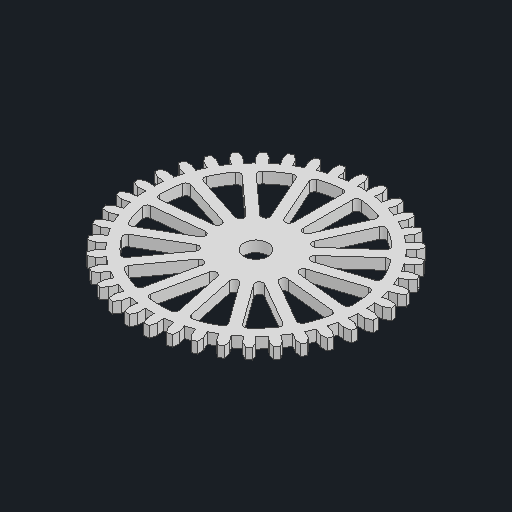
# Autodesk Inventor part: M3_38
Saved by Autodesk Inventor 2027.1 (Build 311270010, 270A)
## iProperties
Created: 2024-04-01
Part Number: M3_38
Material: 一般
Document SubType Name: モデリング
Designer: hibik
Density: 1 g/cm^3
Appearance: 既定
Sheet Metal Rule: Default
Author: hibik
Autodesk Inventor part; units mm, degrees
(part 1 of 2)
ref_plane "YZ Plane" through (0, 0, 0) normal (1, 0, 0) x (0, 1, 0)
ref_plane "XZ Plane" through (0, 0, 0) normal (0, 1, 0) x (-1, 0, 0)
ref_plane "XY Plane" through (0, 0, 0) normal (0, 0, 1) x (1, 0, 0)
sketch "スケッチ1" plane through (0, 0, 0) normal (0, 1, 0) x (-1, 0, 0)
  circle A0 centre (0, 0) radius 57 construction
  circle A1 centre (0, 0) radius 60 construction
  line L0 (60, 1.2454) -> (60, -1.2454)
  line L1 (60, 1.2454) -> (56.9513, 2.355)
  line L2 (60, -1.2454) -> (56.9513, -2.355)
  line L3 (84, 0) -> (-84, 0) projected
  circle A2 centre (0, 0) radius 53.25
  line L4 (56.9513, -2.355) -> (53.2045, -2.2001)
  line L5 (56.9513, 2.355) -> (53.2045, 2.2001)
  line L6 (55.787, 11.6968) -> (52.1168, 10.9272)
  line L7 (58.9767, 11.1041) -> (55.787, 11.6968)
  line L8 (58.9767, 11.1041) -> (59.3867, 8.6473)
  line L9 (59.3867, 8.6473) -> (56.5622, 7.051)
  line L10 (56.5622, 7.051) -> (52.841, 6.5871)
  line L11 (53.1009, 20.7195) -> (49.6074, 19.3563)
  line L12 (56.3447, 20.6599) -> (53.1009, 20.7195)
  line L13 (56.3447, 20.6599) -> (57.1534, 18.3041)
  line L14 (57.1534, 18.3041) -> (54.6302, 16.2647)
  line L15 (54.6302, 16.2647) -> (51.0361, 15.1946)
  line L16 (48.9663, 29.177) -> (45.7449, 27.2575)
  line L17 (52.1757, 29.6521) -> (48.9663, 29.177)
  line L18 (52.1757, 29.6521) -> (53.3612, 27.4616)
  line L19 (53.3612, 27.4616) -> (51.2081, 25.0347)
  line L20 (51.2081, 25.0347) -> (47.8391, 23.3877)
  line L21 (43.4961, 36.8387) -> (40.6345, 34.4151)
  line L22 (46.5835, 37.8355) -> (43.4961, 36.8387)
  line L23 (46.5835, 37.8355) -> (48.1134, 35.87)
  line L24 (48.1134, 35.87) -> (46.3891, 33.1218)
  line L25 (46.3891, 33.1218) -> (43.3372, 30.9427)
  line L26 (36.8395, 43.4955) -> (34.4158, 40.6339)
  line L27 (39.7206, 44.9869) -> (36.8395, 43.4955)
  line L28 (39.7206, 44.9869) -> (41.5531, 43.3)
  line L29 (41.5531, 43.3) -> (40.3047, 40.3055)
  line L30 (40.3047, 40.3055) -> (37.6531, 37.6538)
  line L31 (29.1779, 48.9658) -> (27.2583, 45.7444)
  line L32 (31.7743, 50.9111) -> (29.1779, 48.9658)
  line L33 (31.7743, 50.9111) -> (33.8595, 49.5488)
  line L34 (33.8595, 49.5488) -> (33.121, 46.3897)
  line L35 (33.121, 46.3897) -> (30.9419, 43.3377)
  line L36 (20.7204, 53.1005) -> (19.3573, 49.607)
  line L37 (22.9612, 55.4467) -> (20.7204, 53.1005)
  line L38 (22.9612, 55.4467) -> (25.2422, 54.4461)
  line L39 (25.2422, 54.4461) -> (25.0337, 51.2085)
  line L40 (25.0337, 51.2085) -> (23.3868, 47.8395)
  line L41 (11.6978, 55.7868) -> (10.9282, 52.1166)
  line L42 (13.5219, 58.4697) -> (11.6978, 55.7868)
  line L43 (13.5219, 58.4697) -> (15.9364, 57.8583)
  line L44 (15.9364, 57.8583) -> (16.2637, 54.6305)
  line L45 (16.2637, 54.6305) -> (15.1937, 51.0364)
  line L46 (2.356, 56.9513) -> (2.201, 53.2045)
  line L47 (3.7136, 59.8979) -> (2.356, 56.9513)
  line L48 (3.7136, 59.8979) -> (6.1959, 59.6922)
  line L49 (6.1959, 59.6922) -> (7.05, 56.5623)
  line L50 (7.05, 56.5623) -> (6.5861, 52.8411)
  line L51 (-7.05, 56.5623) -> (-6.5861, 52.8411)
  line L52 (-6.1959, 59.6922) -> (-7.05, 56.5623)
  line L53 (-6.1959, 59.6922) -> (-3.7136, 59.8979)
  line L54 (-3.7136, 59.8979) -> (-2.356, 56.9513)
  line L55 (-2.356, 56.9513) -> (-2.201, 53.2045)
  line L56 (-16.2637, 54.6305) -> (-15.1937, 51.0364)
  line L57 (-15.9364, 57.8583) -> (-16.2637, 54.6305)
  line L58 (-15.9364, 57.8583) -> (-13.5219, 58.4697)
  line L59 (-13.5219, 58.4697) -> (-11.6978, 55.7868)
  line L60 (-11.6978, 55.7868) -> (-10.9282, 52.1166)
  line L61 (-25.0337, 51.2085) -> (-23.3868, 47.8395)
  line L62 (-25.2422, 54.4461) -> (-25.0337, 51.2085)
  line L63 (-25.2422, 54.4461) -> (-22.9612, 55.4467)
  line L64 (-22.9612, 55.4467) -> (-20.7204, 53.1005)
  line L65 (-20.7204, 53.1005) -> (-19.3573, 49.607)
  line L66 (-33.121, 46.3897) -> (-30.9419, 43.3377)
  line L67 (-33.8595, 49.5488) -> (-33.121, 46.3897)
  line L68 (-33.8595, 49.5488) -> (-31.7743, 50.9111)
  line L69 (-31.7743, 50.9111) -> (-29.1779, 48.9658)
  line L70 (-29.1779, 48.9658) -> (-27.2583, 45.7444)
  line L71 (-40.3047, 40.3055) -> (-37.6531, 37.6538)
  line L72 (-41.5531, 43.3) -> (-40.3047, 40.3055)
  line L73 (-41.5531, 43.3) -> (-39.7206, 44.9869)
  line L74 (-39.7206, 44.9869) -> (-36.8395, 43.4955)
  line L75 (-36.8395, 43.4955) -> (-34.4158, 40.6339)
  line L76 (-46.3891, 33.1218) -> (-43.3372, 30.9427)
  line L77 (-48.1134, 35.87) -> (-46.3891, 33.1218)
  line L78 (-48.1134, 35.87) -> (-46.5835, 37.8355)
  line L79 (-46.5835, 37.8355) -> (-43.4961, 36.8387)
  line L80 (-43.4961, 36.8387) -> (-40.6345, 34.4151)
  line L81 (-51.2081, 25.0347) -> (-47.8391, 23.3877)
  line L82 (-53.3612, 27.4616) -> (-51.2081, 25.0347)
  line L83 (-53.3612, 27.4616) -> (-52.1757, 29.6521)
  line L84 (-52.1757, 29.6521) -> (-48.9663, 29.177)
  line L85 (-48.9663, 29.177) -> (-45.7449, 27.2575)
  line L86 (-54.6302, 16.2647) -> (-51.0361, 15.1946)
  line L87 (-57.1534, 18.3041) -> (-54.6302, 16.2647)
  line L88 (-57.1534, 18.3041) -> (-56.3447, 20.6599)
  line L89 (-56.3447, 20.6599) -> (-53.1009, 20.7195)
  line L90 (-53.1009, 20.7195) -> (-49.6074, 19.3563)
  line L91 (-56.5622, 7.051) -> (-52.841, 6.5871)
  line L92 (-59.3867, 8.6473) -> (-56.5622, 7.051)
  line L93 (-59.3867, 8.6473) -> (-58.9767, 11.1041)
  line L94 (-58.9767, 11.1041) -> (-55.787, 11.6968)
  line L95 (-55.787, 11.6968) -> (-52.1168, 10.9272)
  line L96 (-56.9513, -2.355) -> (-53.2045, -2.2001)
  line L97 (-60, -1.2454) -> (-56.9513, -2.355)
  line L98 (-60, -1.2454) -> (-60, 1.2454)
  line L99 (-60, 1.2454) -> (-56.9513, 2.355)
  line L100 (-56.9513, 2.355) -> (-53.2045, 2.2001)
  line L101 (-55.787, -11.6968) -> (-52.1168, -10.9272)
  line L102 (-58.9767, -11.1041) -> (-55.787, -11.6968)
  line L103 (-58.9767, -11.1041) -> (-59.3867, -8.6473)
  line L104 (-59.3867, -8.6473) -> (-56.5622, -7.051)
  line L105 (-56.5622, -7.051) -> (-52.841, -6.5871)
  line L106 (-53.1009, -20.7195) -> (-49.6074, -19.3563)
  line L107 (-56.3447, -20.6599) -> (-53.1009, -20.7195)
  line L108 (-56.3447, -20.6599) -> (-57.1534, -18.3041)
  line L109 (-57.1534, -18.3041) -> (-54.6302, -16.2647)
  line L110 (-54.6302, -16.2647) -> (-51.0361, -15.1946)
  line L111 (-48.9663, -29.177) -> (-45.7449, -27.2575)
  line L112 (-52.1757, -29.6521) -> (-48.9663, -29.177)
  line L113 (-52.1757, -29.6521) -> (-53.3612, -27.4616)
  line L114 (-53.3612, -27.4616) -> (-51.2081, -25.0347)
  line L115 (-51.2081, -25.0347) -> (-47.8391, -23.3877)
  line L116 (-43.4961, -36.8387) -> (-40.6345, -34.4151)
  line L117 (-46.5835, -37.8355) -> (-43.4961, -36.8387)
  line L118 (-46.5835, -37.8355) -> (-48.1134, -35.87)
  line L119 (-48.1134, -35.87) -> (-46.3891, -33.1218)
  line L120 (-46.3891, -33.1218) -> (-43.3372, -30.9427)
  line L121 (-36.8395, -43.4955) -> (-34.4158, -40.6339)
  line L122 (-39.7206, -44.9869) -> (-36.8395, -43.4955)
  line L123 (-39.7206, -44.9869) -> (-41.5531, -43.3)
  line L124 (-41.5531, -43.3) -> (-40.3047, -40.3055)
  line L125 (-40.3047, -40.3055) -> (-37.6531, -37.6538)
  line L126 (-29.1779, -48.9658) -> (-27.2583, -45.7444)
  line L127 (-31.7743, -50.9111) -> (-29.1779, -48.9658)
  line L128 (-31.7743, -50.9111) -> (-33.8595, -49.5488)
  line L129 (-33.8595, -49.5488) -> (-33.121, -46.3897)
  line L130 (-33.121, -46.3897) -> (-30.9419, -43.3377)
  line L131 (-20.7204, -53.1005) -> (-19.3573, -49.607)
  line L132 (-22.9612, -55.4467) -> (-20.7204, -53.1005)
  line L133 (-22.9612, -55.4467) -> (-25.2422, -54.4461)
  line L134 (-25.2422, -54.4461) -> (-25.0337, -51.2085)
  line L135 (-25.0337, -51.2085) -> (-23.3868, -47.8395)
  line L136 (-11.6978, -55.7868) -> (-10.9282, -52.1166)
  line L137 (-13.5219, -58.4697) -> (-11.6978, -55.7868)
  line L138 (-13.5219, -58.4697) -> (-15.9364, -57.8583)
  line L139 (-15.9364, -57.8583) -> (-16.2637, -54.6305)
  line L140 (-16.2637, -54.6305) -> (-15.1937, -51.0364)
  line L141 (-2.356, -56.9513) -> (-2.201, -53.2045)
  line L142 (-3.7136, -59.8979) -> (-2.356, -56.9513)
  line L143 (-3.7136, -59.8979) -> (-6.1959, -59.6922)
  line L144 (-6.1959, -59.6922) -> (-7.05, -56.5623)
  line L145 (-7.05, -56.5623) -> (-6.5861, -52.8411)
  line L146 (7.05, -56.5623) -> (6.5861, -52.8411)
  line L147 (6.1959, -59.6922) -> (7.05, -56.5623)
  line L148 (6.1959, -59.6922) -> (3.7136, -59.8979)
  line L149 (3.7136, -59.8979) -> (2.356, -56.9513)
  line L150 (2.356, -56.9513) -> (2.201, -53.2045)
  line L151 (16.2637, -54.6305) -> (15.1937, -51.0364)
  line L152 (15.9364, -57.8583) -> (16.2637, -54.6305)
  line L153 (15.9364, -57.8583) -> (13.5219, -58.4697)
  line L154 (13.5219, -58.4697) -> (11.6978, -55.7868)
  line L155 (11.6978, -55.7868) -> (10.9282, -52.1166)
  line L156 (25.0337, -51.2085) -> (23.3868, -47.8395)
  line L157 (25.2422, -54.4461) -> (25.0337, -51.2085)
  line L158 (25.2422, -54.4461) -> (22.9612, -55.4467)
  line L159 (22.9612, -55.4467) -> (20.7204, -53.1005)
  line L160 (20.7204, -53.1005) -> (19.3573, -49.607)
  line L161 (33.121, -46.3897) -> (30.9419, -43.3377)
  line L162 (33.8595, -49.5488) -> (33.121, -46.3897)
  line L163 (33.8595, -49.5488) -> (31.7743, -50.9111)
  line L164 (31.7743, -50.9111) -> (29.1779, -48.9658)
  line L165 (29.1779, -48.9658) -> (27.2583, -45.7444)
  line L166 (40.3047, -40.3055) -> (37.6531, -37.6538)
  line L167 (41.5531, -43.3) -> (40.3047, -40.3055)
  line L168 (41.5531, -43.3) -> (39.7206, -44.9869)
  line L169 (39.7206, -44.9869) -> (36.8395, -43.4955)
  line L170 (36.8395, -43.4955) -> (34.4158, -40.6339)
  line L171 (46.3891, -33.1218) -> (43.3372, -30.9427)
  line L172 (48.1134, -35.87) -> (46.3891, -33.1218)
  line L173 (48.1134, -35.87) -> (46.5835, -37.8355)
  line L174 (46.5835, -37.8355) -> (43.4961, -36.8387)
  line L175 (43.4961, -36.8387) -> (40.6345, -34.4151)
  line L176 (51.2081, -25.0347) -> (47.8391, -23.3877)
  line L177 (53.3612, -27.4616) -> (51.2081, -25.0347)
  line L178 (53.3612, -27.4616) -> (52.1757, -29.6521)
  line L179 (52.1757, -29.6521) -> (48.9663, -29.177)
  line L180 (48.9663, -29.177) -> (45.7449, -27.2575)
  line L181 (54.6302, -16.2647) -> (51.0361, -15.1946)
  line L182 (57.1534, -18.3041) -> (54.6302, -16.2647)
  line L183 (57.1534, -18.3041) -> (56.3447, -20.6599)
  line L184 (56.3447, -20.6599) -> (53.1009, -20.7195)
  line L185 (53.1009, -20.7195) -> (49.6074, -19.3563)
  line L186 (56.5622, -7.051) -> (52.841, -6.5871)
  line L187 (59.3867, -8.6473) -> (56.5622, -7.051)
  line L188 (59.3867, -8.6473) -> (58.9767, -11.1041)
  line L189 (58.9767, -11.1041) -> (55.787, -11.6968)
  line L190 (55.787, -11.6968) -> (52.1168, -10.9272)
  circle A3 centre (0, 0) radius 11
  point P0 (60, 0)
  point P1 (59.1817, 9.8757)
  point P2 (56.749, 19.482)
  point P3 (52.7684, 28.5568)
  point P4 (47.3484, 36.8528)
  point P5 (40.6369, 44.1434)
  point P6 (32.8169, 50.23)
  point P7 (24.1017, 54.9464)
  point P8 (14.7291, 58.164)
  point P9 (4.9548, 59.7951)
  point P10 (-4.9548, 59.7951)
  point P11 (-14.7291, 58.164)
  point P12 (-24.1017, 54.9464)
  point P13 (-32.8169, 50.23)
  point P14 (-40.6369, 44.1434)
  point P15 (-47.3484, 36.8528)
  point P16 (-52.7684, 28.5568)
  point P17 (-56.749, 19.482)
  point P18 (-59.1817, 9.8757)
  point P19 (-60, 0)
  point P20 (-59.1817, -9.8757)
  point P21 (-56.749, -19.482)
  point P22 (-52.7684, -28.5568)
  point P23 (-47.3484, -36.8528)
  point P24 (-40.6369, -44.1434)
  point P25 (-32.8169, -50.23)
  point P26 (-24.1017, -54.9464)
  point P27 (-14.7291, -58.164)
  point P28 (-4.9548, -59.7951)
  point P29 (4.9548, -59.7951)
  point P30 (14.7291, -58.164)
  point P31 (24.1017, -54.9464)
  point P32 (32.8169, -50.23)
  point P33 (40.6369, -44.1434)
  point P34 (47.3484, -36.8528)
  point P35 (52.7684, -28.5568)
  point P36 (56.749, -19.482)
  point P37 (59.1817, -9.8757)
  point P38 (-43.3372, -30.9427)
  point P39 (-40.6345, -34.4151)
  point P40 (-37.6531, -37.6538)
  point P41 (-34.4158, -40.6339)
  point P42 (-30.9419, -43.3377)
  point P43 (-19.3573, -49.607)
  point P44 (-15.1937, -51.0364)
  point P45 (-10.9282, -52.1166)
  point P46 (-6.5861, -52.8411)
  point P47 (-2.201, -53.2045)
  point P48 (2.201, -53.2045)
  point P49 (10.9282, -52.1166)
  point P50 (15.1937, -51.0364)
  point P51 (19.3573, -49.607)
  point P52 (23.3868, -47.8395)
  point P53 (27.2583, -45.7444)
  point P54 (30.9419, -43.3377)
  point P55 (34.4158, -40.6339)
  point P56 (37.6531, -37.6538)
  point P57 (40.6345, -34.4151)
  point P58 (43.3372, -30.9427)
  point P59 (45.7449, -27.2575)
  point P60 (47.8391, -23.3877)
  point P61 (49.6074, -19.3563)
  point P62 (51.0361, -15.1946)
  point P63 (52.1168, -10.9272)
  point P64 (52.841, -6.5871)
  point P65 (52.841, 6.5871)
  point P66 (52.1168, 10.9272)
  point P67 (49.6074, 19.3563)
  point P68 (45.7449, 27.2575)
  point P69 (40.6345, 34.4151)
  point P70 (37.6531, 37.6538)
  point P71 (34.4158, 40.6339)
  point P72 (27.2583, 45.7444)
  point P73 (19.3573, 49.607)
  point P74 (15.1937, 51.0364)
  point P75 (10.9282, 52.1166)
  point P76 (6.5861, 52.8411)
  point P77 (2.201, 53.2045)
  point P78 (-2.201, 53.2045)
  point P79 (-6.5861, 52.8411)
  point P80 (-10.9282, 52.1166)
  point P81 (-15.1937, 51.0364)
  point P82 (-19.3573, 49.607)
  point P83 (-23.3868, 47.8395)
  point P84 (-27.2583, 45.7444)
  point P85 (-30.9419, 43.3377)
  point P86 (-34.4158, 40.6339)
  point P87 (-37.6531, 37.6538)
  point P88 (-43.3372, 30.9427)
  point P89 (-45.7449, 27.2575)
  point P90 (-47.8391, 23.3877)
  point P91 (-49.6074, 19.3563)
  point P92 (-51.0361, 15.1946)
  point P93 (-52.1168, 10.9272)
  point P94 (-52.841, -6.5871)
  point P95 (-52.1168, -10.9272)
  point P96 (-51.0361, -15.1946)
  point P97 (-49.6074, -19.3563)
  point P98 (-47.8391, -23.3877)
  dimension "d5" = 106.5
  dimension "d0" = 114
  dimension "d1" = 120
  dimension "d3" = 20
  dimension "d4" = 20
  dimension "d14" = 4.71
  dimension "d18" = 360
  dimension "d24" = 22
  constraints: 380 end point, 77 point on line, 6 coincident, 3 centre point, 2 point on circle, 1 midpoint, 1 tangent, 1 vertical, 496 other
  measures "d0" diameter of A0
  measures "d1" diameter of A1
  measures "d3" angle of L3 L1
  measures "d4" angle of L3 L2
  measures "d14" distance of L2.end L1.end
  measures "d24" diameter of A3
extrude "押し出し1" add sketch "スケッチ1" along normal blind 5.5 contours L0 L3 A2 L5 L1 | L0 L2 L4 A2 L3 | A2 L3 A3 | L3 A3 A2 | A2 L6 L7 L8 L9 L10 | L186 L187 L188 L189 L190 A2 | A2 L96 L97 L98 L3 | L3 L98 L99 L100 A2 | A2 L11 L12 L13 L14 L15 | L181 L182 L183 L184 L185 A2 | L91 L92 L93 L94 L95 A2 | A2 L101 L102 L103 L104 L105 | A2 L16 L17 L18 L19 L20 | L176 L177 L178 L179 L180 A2 | L86 L87 L88 L89 L90 A2 | A2 L106 L107 L108 L109 L110 | A2 L21 L22 L23 L24 L25 | L171 L172 L173 L174 L175 A2 | L81 L82 L83 L84 L85 A2 | A2 L111 L112 L113 L114 L115 | A2 L26 L27 L28 L29 L30 | L166 L167 L168 L169 L170 A2 | L76 L77 L78 L79 L80 A2 | A2 L116 L117 L118 L119 L120 | A2 L31 L32 L33 L34 L35 | L161 L162 L163 L164 L165 A2 | L71 L72 L73 L74 L75 A2 | A2 L121 L122 L123 L124 L125 | A2 L36 L37 L38 L39 L40 | L156 L157 L158 L159 L160 A2 | L66 L67 L68 L69 L70 A2 | A2 L126 L127 L128 L129 L130 | A2 L41 L42 L43 L44 L45 | L151 L152 L153 L154 L155 A2 | L61 L62 L63 L64 L65 A2 | A2 L131 L132 L133 L134 L135 | A2 L46 L47 L48 L49 L50 | L146 L147 L148 L149 L150 A2 | L56 L57 L58 L59 L60 A2 | A2 L136 L137 L138 L139 L140 | A2 L51 L52 L53 L54 L55 | L141 L142 L143 L144 L145 A2
sketch "スケッチ2" plane through (0, 5.5, 0) normal (0, 1, 0) x (1, 0, 0)
  circle A0 centre (0, 0) radius 11 projected
  arc A1 (-15.1937, 51.0364) -> (-19.3573, 49.607) centre (0, 0) ccw projected
  circle A2 centre (0, 0) radius 16
  circle A3 centre (0, 0) radius 48.25
  line L0 (-2.5, 48.25) -> (2.5, 48.25) construction
  line L1 (2.5, 48.25) -> (2.5, 0)
  line L2 (2.5, 0) -> (-2.5, 0)
  line L3 (-2.5, 0) -> (-2.5, 48.25)
  point P0 (-2.5, 15.8035)
  point P1 (-2.5, 48.1852)
  point P2 (2.5, 48.1852)
  point P3 (2.5, 15.8035)
  dimension "d25" = 5
  dimension "d26" = 5
  dimension "d27" = 5
  constraints: 8 end point, 3 coincident, 2 centre point, 2 parallel, 1 horizontal, 1 midpoint, 1 perpendicular, 1 tangent
  measures "d25" radial gap between concentric circles of A3 A1
  measures "d26" radial gap between concentric circles of A2 A0
  measures "d27" distance of L0.start L0.end
extrude "押し出し2" cut sketch "スケッチ2" against normal through all contours L1 A3 L3 A2 | A2 L3 A3 L1
sketch "スケッチ4" plane through (0, 5.5, 0) normal (0, 1, 0) x (1, 0, 0)
  line L0 (-2.5, 48.1852) -> (2.5, 48.1852) construction
  line L1 (2.5, 48.1852) -> (2.5, 0)
  line L2 (2.5, 0) -> (-2.5, 0)
  line L3 (-2.5, 0) -> (-2.5, 48.1852)
  circle A0 centre (0, 0) radius 48.25 projected
  circle A1 centre (0, 0) radius 16 projected
  point P0 (-2.5, 15.8035)
  point P1 (2.5, 15.8035)
  point P2 (-2.5, 48.1852)
  dimension "d32" = 5
  constraints: 8 end point, 2 parallel, 1 coincident, 1 horizontal, 1 midpoint, 1 perpendicular, 2 other
  measures "d32" distance of L1.end L2.end
extrude "押し出し4" add sketch "スケッチ4" against normal up to surface (5.5 mm away) contours L1 A1 L3 A0 picked at (0.2779, 26.733)
pattern_circular "円形状パターン1" count 15 over 360 about axis through (0, -10, 0) along (0, 1, 0) of "押し出し4"
fillet "フィレット1" radius 2 4 edges at (7.5729, 2.75, 47.652) (-7.5729, 2.75, 47.652) (0.8404, 2.75, 15.9779) (-0.8404, 2.75, 15.9779)
pattern_circular "円形状パターン2" count 15 over 360 about axis through (0, -10, 0) along (0, 1, 0) of "フィレット1"
sketch "スケッチ5" plane through (0, 0, 0) normal (0, -1, 0) x (1, 0, 0)
  circle A0 centre (0, 0) radius 6 projected
  arc A1 (38.6136, 25.1803) -> (39.2402, 28.0762) centre (37.6136, 26.9124) ccw projected
  line L0 (38.6136, 25.1803) -> (17.0845, 12.7505) projected
  arc A2 (14.4664, 15.6581) -> (17.0845, 12.7505) centre (16.0845, 14.4825) ccw projected
  line L1 (14.4664, 15.6581) -> (29.0786, 35.77) projected
  arc A3 (32.0241, 36.0904) -> (29.0786, 35.77) centre (30.6967, 34.5945) ccw projected
  arc A4 (39.2402, 28.0762) -> (32.0241, 36.0904) centre (0, 0) ccw projected
  arc A5 (21.0062, -41.0342) -> (23.8207, -41.96) centre (22.8333, -40.2207) ccw projected
  line L2 (21.0062, -41.0342) -> (10.8948, -18.3237) projected
  arc A6 (14.0602, -16.0239) -> (10.8948, -18.3237) centre (12.7219, -17.5102) ccw projected
  line L3 (14.0602, -16.0239) -> (32.5345, -32.6583) projected
  arc A7 (32.5453, -35.6211) -> (32.5345, -32.6583) centre (31.1963, -34.1446) ccw projected
  arc A8 (23.8207, -41.96) -> (32.5453, -35.6211) centre (0, 0) ccw projected
  arc A9 (-43.0051, -16.6019) -> (-44.22, -19.3042) centre (-42.3871, -18.504) ccw projected
  line L4 (-43.0051, -16.6019) -> (-19.3621, -8.9198) projected
  arc A10 (-17.4058, -12.3082) -> (-19.3621, -8.9198) centre (-18.7441, -10.8219) ccw projected
  line L5 (-17.4058, -12.3082) -> (-35.8802, -28.9426) projected
  arc A11 (-38.8279, -28.6436) -> (-35.8802, -28.9426) centre (-37.2185, -27.4563) ccw projected
  arc A12 (-44.22, -19.3042) -> (-38.8279, -28.6436) centre (0, 0) ccw projected
  arc A13 (-12.0157, 44.5049) -> (-14.5761, 45.9956) centre (-13.972, 44.0891) ccw projected
  line L6 (-12.0157, 44.5049) -> (-6.847, 20.1884) projected
  arc A14 (-10.4214, 18.597) -> (-6.847, 20.1884) centre (-8.8033, 19.7726) ccw projected
  line L7 (-10.4214, 18.597) -> (-25.0335, 38.709) projected
  arc A15 (-24.4281, 41.6093) -> (-25.0335, 38.709) centre (-23.4155, 39.8845) ccw projected
  arc A16 (-14.5761, 45.9956) -> (-24.4281, 41.6093) centre (0, 0) ccw projected
  arc A17 (-46.0397, 2.3252) -> (-48.2487, 0.3507) centre (-46.2488, 0.3362) ccw projected
  line L8 (-46.0397, 2.3252) -> (-21.3162, -0.2733) projected
  arc A18 (-20.9072, -4.1645) -> (-21.3162, -0.2733) centre (-21.5252, -2.2624) ccw projected
  line L9 (-20.9072, -4.1645) -> (-44.5502, -11.8466) projected
  arc A19 (-47.1215, -10.3745) -> (-44.5502, -11.8466) centre (-45.1682, -9.9445) ccw projected
  arc A20 (-48.2487, 0.3507) -> (-47.1215, -10.3745) centre (0, 0) ccw projected
  arc A21 (2.5, -46.0306) -> (4.6946, -48.0211) centre (4.5, -46.0306) ccw projected
  line L10 (2.5, -46.0306) -> (2.5, -21.1708) projected
  arc A22 (6.3271, -20.3574) -> (2.5, -21.1708) centre (4.5, -21.1708) ccw projected
  line L11 (6.3271, -20.3574) -> (16.4385, -43.0679) projected
  arc A23 (15.2432, -45.7789) -> (16.4385, -43.0679) centre (14.6114, -43.8813) ccw projected
  arc A24 (4.6946, -48.0211) -> (15.2432, -45.7789) centre (0, 0) ccw projected
  arc A25 (45.5171, 7.2978) -> (47.2673, 9.6884) centre (45.308, 9.2869) ccw projected
  line L12 (45.5171, 7.2978) -> (20.7935, 4.6993) projected
  arc A26 (19.5845, 8.4204) -> (20.7935, 4.6993) centre (20.5845, 6.6883) ccw projected
  line L13 (19.5845, 8.4204) -> (41.1136, 20.8502) projected
  arc A27 (43.9348, 19.9449) -> (41.1136, 20.8502) centre (42.1136, 19.1182) ccw projected
  arc A28 (47.2673, 9.6884) -> (43.9348, 19.9449) centre (0, 0) ccw projected
  arc A29 (25.0335, 38.709) -> (24.4281, 41.6093) centre (23.4155, 39.8845) ccw projected
  line L14 (25.0335, 38.709) -> (10.4214, 18.597) projected
  arc A30 (6.847, 20.1884) -> (10.4214, 18.597) centre (8.8033, 19.7726) ccw projected
  line L15 (6.847, 20.1884) -> (12.0157, 44.5049) projected
  arc A31 (14.5761, 45.9956) -> (12.0157, 44.5049) centre (13.972, 44.0891) ccw projected
  arc A32 (24.4281, 41.6093) -> (14.5761, 45.9956) centre (0, 0) ccw projected
  arc A33 (35.8802, -28.9426) -> (38.8279, -28.6436) centre (37.2185, -27.4563) ccw projected
  line L16 (35.8802, -28.9426) -> (17.4058, -12.3082) projected
  arc A34 (19.3621, -8.9198) -> (17.4058, -12.3082) centre (18.7441, -10.8219) ccw projected
  line L17 (19.3621, -8.9198) -> (43.0051, -16.6019) projected
  arc A35 (44.22, -19.3042) -> (43.0051, -16.6019) centre (42.3871, -18.504) ccw projected
  arc A36 (38.8279, -28.6436) -> (44.22, -19.3042) centre (0, 0) ccw projected
  arc A37 (-32.5345, -32.6583) -> (-32.5453, -35.6211) centre (-31.1963, -34.1446) ccw projected
  line L18 (-32.5345, -32.6583) -> (-14.0602, -16.0239) projected
  arc A38 (-10.8948, -18.3237) -> (-14.0602, -16.0239) centre (-12.7219, -17.5102) ccw projected
  line L19 (-10.8948, -18.3237) -> (-21.0062, -41.0342) projected
  arc A39 (-23.8207, -41.96) -> (-21.0062, -41.0342) centre (-22.8333, -40.2207) ccw projected
  arc A40 (-32.5453, -35.6211) -> (-23.8207, -41.96) centre (0, 0) ccw projected
  arc A41 (-29.0786, 35.77) -> (-32.0241, 36.0904) centre (-30.6967, 34.5945) ccw projected
  line L20 (-29.0786, 35.77) -> (-14.4664, 15.6581) projected
  arc A42 (-17.0845, 12.7505) -> (-14.4664, 15.6581) centre (-16.0845, 14.4825) ccw projected
  line L21 (-17.0845, 12.7505) -> (-38.6136, 25.1803) projected
  arc A43 (-39.2402, 28.0762) -> (-38.6136, 25.1803) centre (-37.6136, 26.9124) ccw projected
  arc A44 (-32.0241, 36.0904) -> (-39.2402, 28.0762) centre (0, 0) ccw projected
  arc A45 (-41.1136, 20.8502) -> (-43.9348, 19.9449) centre (-42.1136, 19.1182) ccw projected
  line L22 (-41.1136, 20.8502) -> (-19.5845, 8.4204) projected
  arc A46 (-20.7935, 4.6993) -> (-19.5845, 8.4204) centre (-20.5845, 6.6883) ccw projected
  line L23 (-20.7935, 4.6993) -> (-45.5171, 7.2978) projected
  arc A47 (-47.2673, 9.6884) -> (-45.5171, 7.2978) centre (-45.308, 9.2869) ccw projected
  arc A48 (-43.9348, 19.9449) -> (-47.2673, 9.6884) centre (0, 0) ccw projected
  arc A49 (-16.4385, -43.0679) -> (-15.2432, -45.7789) centre (-14.6114, -43.8813) ccw projected
  line L24 (-16.4385, -43.0679) -> (-6.3271, -20.3574) projected
  arc A50 (-2.5, -21.1708) -> (-6.3271, -20.3574) centre (-4.5, -21.1708) ccw projected
  line L25 (-2.5, -21.1708) -> (-2.5, -46.0306) projected
  arc A51 (-4.6946, -48.0211) -> (-2.5, -46.0306) centre (-4.5, -46.0306) ccw projected
  arc A52 (-15.2432, -45.7789) -> (-4.6946, -48.0211) centre (0, 0) ccw projected
  arc A53 (44.5502, -11.8466) -> (47.1215, -10.3745) centre (45.1682, -9.9445) ccw projected
  line L26 (44.5502, -11.8466) -> (20.9072, -4.1645) projected
  arc A54 (21.3162, -0.2733) -> (20.9072, -4.1645) centre (21.5252, -2.2624) ccw projected
  line L27 (21.3162, -0.2733) -> (46.0397, 2.3252) projected
  arc A55 (48.2487, 0.3507) -> (46.0397, 2.3252) centre (46.2488, 0.3362) ccw projected
  arc A56 (47.1215, -10.3745) -> (48.2487, 0.3507) centre (0, 0) ccw projected
  line L28 (7.1249, 45.5445) -> (1.9563, 21.228) projected
  arc A57 (-1.9563, 21.228) -> (1.9563, 21.228) centre (0, 21.6438) ccw projected
  line L29 (-1.9563, 21.228) -> (-7.1249, 45.5445) projected
  arc A58 (-5.3921, 47.9478) -> (-7.1249, 45.5445) centre (-5.1686, 45.9603) ccw projected
  arc A59 (5.3921, 47.9478) -> (-5.3921, 47.9478) centre (0, 0) ccw projected
  arc A60 (7.1249, 45.5445) -> (5.3921, 47.9478) centre (5.1686, 45.9603) ccw projected
  arc A61 (41.8431, -55.9299) -> (47.5637, -55.3777) centre (44.3103, -51.581) ccw projected
  arc A62 (47.5637, -55.3777) -> (47.5684, -55.3737) centre (0, 0) ccw projected
  arc A63 (47.5684, -55.3737) -> (48.8465, -54.2496) centre (0, 0) ccw projected
  arc A64 (45.7049, -48.9905) -> (48.8465, -54.2496) centre (60.6207, -43.648) ccw projected
  arc A65 (45.7049, -48.9905) -> (52.1817, -42.0246) centre (0, 0) ccw projected
  arc A66 (57.0784, -40.2623) -> (52.1817, -42.0246) centre (56.0759, -45.1607) ccw projected
  arc A67 (57.0784, -40.2623) -> (62.3485, -37.9693) centre (58.081, -35.3638) ccw projected
  arc A68 (62.3485, -37.9693) -> (62.3516, -37.9641) centre (0, 0) ccw projected
  arc A69 (62.3516, -37.9641) -> (63.2199, -36.5) centre (0, 0) ccw projected
  arc A70 (58.6068, -32.4691) -> (63.2199, -36.5) centre (71.1417, -22.7789) ccw projected
  arc A71 (58.6068, -32.4691) -> (62.6141, -23.8427) centre (0, 0) ccw projected
  arc A72 (66.7266, -20.6535) -> (62.6141, -23.8427) centre (67.2868, -25.622) ccw projected
  arc A73 (66.7266, -20.6535) -> (71.0301, -16.8442) centre (66.1663, -15.685) ccw projected
  arc A74 (71.0301, -16.8442) -> (71.0315, -16.8383) centre (0, 0) ccw projected
  arc A75 (71.0315, -16.8383) -> (71.4048, -15.1776) centre (0, 0) ccw projected
  arc A76 (65.7719, -12.7695) -> (71.4048, -15.1776) centre (74.6989, 0.32) ccw projected
  arc A77 (65.7719, -12.7695) -> (66.9173, -3.3269) centre (0, 0) ccw projected
  arc A78 (69.843, 0.977) -> (66.9173, -3.3269) centre (71.9112, -3.5752) ccw projected
  arc A79 (69.843, 0.977) -> (72.7588, 5.9297) centre (67.7748, 5.5292) ccw projected
  arc A80 (72.7588, 5.9297) -> (72.7583, 5.9358) centre (0, 0) ccw projected
  arc A81 (72.7583, 5.9358) -> (72.6001, 7.6306) centre (0, 0) ccw projected
  arc A82 (66.4988, 8.1802) -> (72.6001, 7.6306) centre (70.944, 23.3875) ccw projected
  arc A83 (66.4988, 8.1802) -> (64.6703, 17.5145) centre (0, 0) ccw projected
  arc A84 (66.1227, 22.5119) -> (64.6703, 17.5145) centre (69.4964, 18.8215) ccw projected
  arc A85 (66.1227, 22.5119) -> (67.3653, 28.1232) centre (62.7491, 26.2022) ccw projected
  arc A86 (67.3653, 28.1232) -> (67.363, 28.1288) centre (0, 0) ccw projected
  arc A87 (67.363, 28.1288) -> (66.6888, 29.6918) centre (0, 0) ccw projected
  arc A88 (60.7163, 28.329) -> (66.6888, 29.6918) centre (60.2446, 44.1658) ccw projected
  arc A89 (60.7163, 28.329) -> (55.832, 37.0376) centre (0, 0) ccw projected
  arc A90 (55.6323, 42.238) -> (55.832, 37.0376) centre (59.9986, 39.8016) ccw projected
  arc A91 (55.6323, 42.238) -> (55.0356, 47.9592) centre (51.2661, 44.6743) ccw projected
  arc A92 (55.0356, 47.9592) -> (54.2496, 48.8465) centre (0, 0) ccw projected
  arc A93 (48.9905, 45.7049) -> (54.2496, 48.8465) centre (43.648, 60.6207) ccw projected
  arc A94 (48.9905, 45.7049) -> (41.6542, 52.4779) centre (0, 0) ccw projected
  arc A95 (39.8572, 57.362) -> (41.6542, 52.4779) centre (44.7627, 56.3942) ccw projected
  arc A96 (39.8572, 57.362) -> (37.5218, 62.6188) centre (34.9518, 58.3299) ccw projected
  arc A97 (37.5218, 62.6188) -> (36.5, 63.2199) centre (0, 0) ccw projected
  arc A98 (32.4691, 58.6068) -> (36.5, 63.2199) centre (22.7789, 71.1417) ccw projected
  arc A99 (32.4691, 58.6068) -> (23.3989, 62.7813) centre (0, 0) ccw projected
  arc A100 (20.1806, 66.8711) -> (23.3989, 62.7813) centre (25.1451, 67.4665) ccw projected
  arc A101 (20.1806, 66.8711) -> (16.3351, 71.1489) centre (15.2162, 66.2757) ccw projected
  arc A102 (16.3351, 71.1489) -> (15.1776, 71.4048) centre (0, 0) ccw projected
  arc A103 (12.7695, 65.7719) -> (15.1776, 71.4048) centre (-0.32, 74.6989) ccw projected
  arc A104 (12.7695, 65.7719) -> (3.3269, 66.9173) centre (0, 0) ccw projected
  arc A105 (-0.977, 69.843) -> (3.3269, 66.9173) centre (3.5752, 71.9112) ccw projected
  arc A106 (-0.977, 69.843) -> (-5.9297, 72.7588) centre (-5.5292, 67.7748) ccw projected
  arc A107 (-5.9297, 72.7588) -> (-5.9358, 72.7583) centre (0, 0) ccw projected
  arc A108 (-5.9358, 72.7583) -> (-7.6306, 72.6001) centre (0, 0) ccw projected
  arc A109 (-8.1802, 66.4988) -> (-7.6306, 72.6001) centre (-23.3875, 70.944) ccw projected
  arc A110 (-8.1802, 66.4988) -> (-17.5145, 64.6703) centre (0, 0) ccw projected
  arc A111 (-22.5119, 66.1227) -> (-17.5145, 64.6703) centre (-18.8215, 69.4964) ccw projected
  arc A112 (-22.5119, 66.1227) -> (-28.1232, 67.3653) centre (-26.2022, 62.7491) ccw projected
  arc A113 (-28.1232, 67.3653) -> (-28.1288, 67.363) centre (0, 0) ccw projected
  arc A114 (-28.1288, 67.363) -> (-29.6918, 66.6888) centre (0, 0) ccw projected
  arc A115 (-28.329, 60.7163) -> (-29.6918, 66.6888) centre (-44.1658, 60.2446) ccw projected
  arc A116 (-28.329, 60.7163) -> (-37.0376, 55.832) centre (0, 0) ccw projected
  arc A117 (-42.238, 55.6323) -> (-37.0376, 55.832) centre (-39.8016, 59.9986) ccw projected
  arc A118 (-42.238, 55.6323) -> (-47.9592, 55.0356) centre (-44.6743, 51.2661) ccw projected
  arc A119 (-47.9592, 55.0356) -> (-48.8465, 54.2496) centre (0, 0) ccw projected
  arc A120 (-45.7049, 48.9905) -> (-48.8465, 54.2496) centre (-60.6207, 43.648) ccw projected
  arc A121 (-45.7049, 48.9905) -> (-52.1817, 42.0246) centre (0, 0) ccw projected
  arc A122 (-57.0784, 40.2623) -> (-52.1817, 42.0246) centre (-56.0759, 45.1607) ccw projected
  arc A123 (-57.0784, 40.2623) -> (-62.3485, 37.9693) centre (-58.081, 35.3638) ccw projected
  arc A124 (-62.3485, 37.9693) -> (-62.3516, 37.9641) centre (0, 0) ccw projected
  arc A125 (-62.3516, 37.9641) -> (-63.2199, 36.5) centre (0, 0) ccw projected
  arc A126 (-58.6068, 32.4691) -> (-63.2199, 36.5) centre (-71.1417, 22.7789) ccw projected
  arc A127 (-58.6068, 32.4691) -> (-62.7813, 23.3989) centre (0, 0) ccw projected
  arc A128 (-66.8711, 20.1806) -> (-62.7813, 23.3989) centre (-67.4665, 25.1451) ccw projected
  arc A129 (-66.8711, 20.1806) -> (-71.1489, 16.3351) centre (-66.2757, 15.2162) ccw projected
  arc A130 (-71.1489, 16.3351) -> (-71.4048, 15.1776) centre (0, 0) ccw projected
  arc A131 (-65.7719, 12.7695) -> (-71.4048, 15.1776) centre (-74.6989, -0.32) ccw projected
  arc A132 (-65.7719, 12.7695) -> (-66.9392, 2.8532) centre (0, 0) ccw projected
  arc A133 (-69.8343, -1.4714) -> (-66.9392, 2.8532) centre (-71.9347, 3.0661) ccw projected
  arc A134 (-69.8343, -1.4714) -> (-72.7144, -6.4507) centre (-67.734, -6.0088) ccw projected
  arc A135 (-72.7144, -6.4507) -> (-72.6001, -7.6306) centre (0, 0) ccw projected
  arc A136 (-66.4988, -8.1802) -> (-72.6001, -7.6306) centre (-70.944, -23.3875) ccw projected
  arc A137 (-66.4988, -8.1802) -> (-64.6703, -17.5145) centre (0, 0) ccw projected
  arc A138 (-66.1227, -22.5119) -> (-64.6703, -17.5145) centre (-69.4964, -18.8215) ccw projected
  arc A139 (-66.1227, -22.5119) -> (-67.3653, -28.1232) centre (-62.7491, -26.2022) ccw projected
  arc A140 (-67.3653, -28.1232) -> (-67.363, -28.1288) centre (0, 0) ccw projected
  arc A141 (-67.363, -28.1288) -> (-66.6888, -29.6918) centre (0, 0) ccw projected
  arc A142 (-60.7163, -28.329) -> (-66.6888, -29.6918) centre (-60.2446, -44.1658) ccw projected
  arc A143 (-60.7163, -28.329) -> (-56.0928, -36.6415) centre (0, 0) ccw projected
  arc A144 (-55.9299, -41.8431) -> (-56.0928, -36.6415) centre (-60.2788, -39.3759) ccw projected
  arc A145 (-55.9299, -41.8431) -> (-55.3777, -47.5637) centre (-51.581, -44.3103) ccw projected
  arc A146 (-55.3777, -47.5637) -> (-55.3737, -47.5684) centre (0, 0) ccw projected
  arc A147 (-55.3737, -47.5684) -> (-54.2496, -48.8465) centre (0, 0) ccw projected
  arc A148 (-48.9905, -45.7049) -> (-54.2496, -48.8465) centre (-43.648, -60.6207) ccw projected
  arc A149 (-48.9905, -45.7049) -> (-41.6542, -52.4779) centre (0, 0) ccw projected
  arc A150 (-39.8572, -57.362) -> (-41.6542, -52.4779) centre (-44.7627, -56.3942) ccw projected
  arc A151 (-39.8572, -57.362) -> (-37.5218, -62.6188) centre (-34.9518, -58.3299) ccw projected
  arc A152 (-37.5218, -62.6188) -> (-36.5, -63.2199) centre (0, 0) ccw projected
  arc A153 (-32.4691, -58.6068) -> (-36.5, -63.2199) centre (-22.7789, -71.1417) ccw projected
  arc A154 (-32.4691, -58.6068) -> (-23.8427, -62.6141) centre (0, 0) ccw projected
  arc A155 (-20.6535, -66.7266) -> (-23.8427, -62.6141) centre (-25.622, -67.2868) ccw projected
  arc A156 (-20.6535, -66.7266) -> (-16.8442, -71.0301) centre (-15.685, -66.1663) ccw projected
  arc A157 (-16.8442, -71.0301) -> (-16.8383, -71.0315) centre (0, 0) ccw projected
  arc A158 (-16.8383, -71.0315) -> (-15.1776, -71.4048) centre (0, 0) ccw projected
  arc A159 (-12.7695, -65.7719) -> (-15.1776, -71.4048) centre (0.32, -74.6989) ccw projected
  arc A160 (-12.7695, -65.7719) -> (-2.8532, -66.9392) centre (0, 0) ccw projected
  arc A161 (1.4714, -69.8343) -> (-2.8532, -66.9392) centre (-3.0661, -71.9347) ccw projected
  arc A162 (1.4714, -69.8343) -> (6.4507, -72.7144) centre (6.0088, -67.734) ccw projected
  arc A163 (6.4507, -72.7144) -> (7.6306, -72.6001) centre (0, 0) ccw projected
  arc A164 (8.1802, -66.4988) -> (7.6306, -72.6001) centre (23.3875, -70.944) ccw projected
  arc A165 (8.1802, -66.4988) -> (17.5145, -64.6703) centre (0, 0) ccw projected
  arc A166 (22.5119, -66.1227) -> (17.5145, -64.6703) centre (18.8215, -69.4964) ccw projected
  arc A167 (22.5119, -66.1227) -> (28.1232, -67.3653) centre (26.2022, -62.7491) ccw projected
  arc A168 (28.1232, -67.3653) -> (28.1288, -67.363) centre (0, 0) ccw projected
  arc A169 (28.1288, -67.363) -> (29.6918, -66.6888) centre (0, 0) ccw projected
  arc A170 (28.329, -60.7163) -> (29.6918, -66.6888) centre (44.1658, -60.2446) ccw projected
  arc A171 (28.329, -60.7163) -> (36.6415, -56.0928) centre (0, 0) ccw projected
  arc A172 (41.8431, -55.9299) -> (36.6415, -56.0928) centre (39.3759, -60.2788) ccw projected
  arc A173 (4.6946, -48.0211) -> (15.2432, -45.7789) centre (0, 0) ccw construction
  arc A174 (2.5, -46.0306) -> (4.6946, -48.0211) centre (4.5, -46.0306) ccw construction
  line L30 (2.5, -46.0306) -> (2.5, -21.1708) construction
  arc A175 (6.3271, -20.3574) -> (2.5, -21.1708) centre (4.5, -21.1708) ccw construction
  line L31 (6.3271, -20.3574) -> (16.4385, -43.0679) construction
  arc A176 (15.2432, -45.7789) -> (16.4385, -43.0679) centre (14.6114, -43.8813) ccw construction
  line L32 (21.0062, -41.0342) -> (10.8948, -18.3237) construction
  arc A177 (14.0602, -16.0239) -> (10.8948, -18.3237) centre (12.7219, -17.5102) ccw construction
  line L33 (14.0602, -16.0239) -> (32.5345, -32.6583) construction
  arc A178 (32.5453, -35.6211) -> (32.5345, -32.6583) centre (31.1963, -34.1446) ccw construction
  arc A179 (23.8207, -41.96) -> (32.5453, -35.6211) centre (0, 0) ccw construction
  arc A180 (21.0062, -41.0342) -> (23.8207, -41.96) centre (22.8333, -40.2207) ccw construction
  line L34 (35.8802, -28.9426) -> (17.4058, -12.3082) construction
  arc A181 (19.3621, -8.9198) -> (17.4058, -12.3082) centre (18.7441, -10.8219) ccw construction
  line L35 (19.3621, -8.9198) -> (43.0051, -16.6019) construction
  arc A182 (44.22, -19.3042) -> (43.0051, -16.6019) centre (42.3871, -18.504) ccw construction
  arc A183 (38.8279, -28.6436) -> (44.22, -19.3042) centre (0, 0) ccw construction
  arc A184 (35.8802, -28.9426) -> (38.8279, -28.6436) centre (37.2185, -27.4563) ccw construction
  line L36 (44.5502, -11.8466) -> (20.9072, -4.1645) construction
  arc A185 (21.3162, -0.2733) -> (20.9072, -4.1645) centre (21.5252, -2.2624) ccw construction
  line L37 (21.3162, -0.2733) -> (46.0397, 2.3252) construction
  arc A186 (48.2487, 0.3507) -> (46.0397, 2.3252) centre (46.2488, 0.3362) ccw construction
  arc A187 (47.1215, -10.3745) -> (48.2487, 0.3507) centre (0, 0) ccw construction
  arc A188 (44.5502, -11.8466) -> (47.1215, -10.3745) centre (45.1682, -9.9445) ccw construction
  line L38 (45.5171, 7.2978) -> (20.7935, 4.6993) construction
  arc A189 (19.5845, 8.4204) -> (20.7935, 4.6993) centre (20.5845, 6.6883) ccw construction
  line L39 (19.5845, 8.4204) -> (41.1136, 20.8502) construction
  arc A190 (43.9348, 19.9449) -> (41.1136, 20.8502) centre (42.1136, 19.1182) ccw construction
  arc A191 (47.2673, 9.6884) -> (43.9348, 19.9449) centre (0, 0) ccw construction
  arc A192 (45.5171, 7.2978) -> (47.2673, 9.6884) centre (45.308, 9.2869) ccw construction
  line L40 (38.6136, 25.1803) -> (17.0845, 12.7505) construction
  arc A193 (14.4664, 15.6581) -> (17.0845, 12.7505) centre (16.0845, 14.4825) ccw construction
  line L41 (14.4664, 15.6581) -> (29.0786, 35.77) construction
  arc A194 (32.0241, 36.0904) -> (29.0786, 35.77) centre (30.6967, 34.5945) ccw construction
  arc A195 (39.2402, 28.0762) -> (32.0241, 36.0904) centre (0, 0) ccw construction
  arc A196 (38.6136, 25.1803) -> (39.2402, 28.0762) centre (37.6136, 26.9124) ccw construction
  line L42 (25.0335, 38.709) -> (10.4214, 18.597) construction
  arc A197 (6.847, 20.1884) -> (10.4214, 18.597) centre (8.8033, 19.7726) ccw construction
  line L43 (6.847, 20.1884) -> (12.0157, 44.5049) construction
  arc A198 (14.5761, 45.9956) -> (12.0157, 44.5049) centre (13.972, 44.0891) ccw construction
  arc A199 (24.4281, 41.6093) -> (14.5761, 45.9956) centre (0, 0) ccw construction
  arc A200 (25.0335, 38.709) -> (24.4281, 41.6093) centre (23.4155, 39.8845) ccw construction
  line L44 (7.1249, 45.5445) -> (1.9563, 21.228) construction
  arc A201 (-1.9563, 21.228) -> (1.9563, 21.228) centre (0, 21.6438) ccw construction
  line L45 (-1.9563, 21.228) -> (-7.1249, 45.5445) construction
  arc A202 (-5.3921, 47.9478) -> (-7.1249, 45.5445) centre (-5.1686, 45.9603) ccw construction
  arc A203 (5.3921, 47.9478) -> (-5.3921, 47.9478) centre (0, 0) ccw construction
  arc A204 (7.1249, 45.5445) -> (5.3921, 47.9478) centre (5.1686, 45.9603) ccw construction
  line L46 (-12.0157, 44.5049) -> (-6.847, 20.1884) construction
  arc A205 (-10.4214, 18.597) -> (-6.847, 20.1884) centre (-8.8033, 19.7726) ccw construction
  line L47 (-10.4214, 18.597) -> (-25.0335, 38.709) construction
  arc A206 (-24.4281, 41.6093) -> (-25.0335, 38.709) centre (-23.4155, 39.8845) ccw construction
  arc A207 (-14.5761, 45.9956) -> (-24.4281, 41.6093) centre (0, 0) ccw construction
  arc A208 (-12.0157, 44.5049) -> (-14.5761, 45.9956) centre (-13.972, 44.0891) ccw construction
  line L48 (-29.0786, 35.77) -> (-14.4664, 15.6581) construction
  arc A209 (-17.0845, 12.7505) -> (-14.4664, 15.6581) centre (-16.0845, 14.4825) ccw construction
  line L49 (-17.0845, 12.7505) -> (-38.6136, 25.1803) construction
  arc A210 (-39.2402, 28.0762) -> (-38.6136, 25.1803) centre (-37.6136, 26.9124) ccw construction
  arc A211 (-32.0241, 36.0904) -> (-39.2402, 28.0762) centre (0, 0) ccw construction
  arc A212 (-29.0786, 35.77) -> (-32.0241, 36.0904) centre (-30.6967, 34.5945) ccw construction
  line L50 (-41.1136, 20.8502) -> (-19.5845, 8.4204) construction
  arc A213 (-20.7935, 4.6993) -> (-19.5845, 8.4204) centre (-20.5845, 6.6883) ccw construction
  line L51 (-20.7935, 4.6993) -> (-45.5171, 7.2978) construction
  arc A214 (-47.2673, 9.6884) -> (-45.5171, 7.2978) centre (-45.308, 9.2869) ccw construction
  arc A215 (-43.9348, 19.9449) -> (-47.2673, 9.6884) centre (0, 0) ccw construction
  arc A216 (-41.1136, 20.8502) -> (-43.9348, 19.9449) centre (-42.1136, 19.1182) ccw construction
  line L52 (-46.0397, 2.3252) -> (-21.3162, -0.2733) construction
  arc A217 (-20.9072, -4.1645) -> (-21.3162, -0.2733) centre (-21.5252, -2.2624) ccw construction
  line L53 (-20.9072, -4.1645) -> (-44.5502, -11.8466) construction
  arc A218 (-47.1215, -10.3745) -> (-44.5502, -11.8466) centre (-45.1682, -9.9445) ccw construction
  arc A219 (-48.2487, 0.3507) -> (-47.1215, -10.3745) centre (0, 0) ccw construction
  arc A220 (-46.0397, 2.3252) -> (-48.2487, 0.3507) centre (-46.2488, 0.3362) ccw construction
  line L54 (-43.0051, -16.6019) -> (-19.3621, -8.9198) construction
  arc A221 (-17.4058, -12.3082) -> (-19.3621, -8.9198) centre (-18.7441, -10.8219) ccw construction
  line L55 (-17.4058, -12.3082) -> (-35.8802, -28.9426) construction
  arc A222 (-38.8279, -28.6436) -> (-35.8802, -28.9426) centre (-37.2185, -27.4563) ccw construction
  arc A223 (-44.22, -19.3042) -> (-38.8279, -28.6436) centre (0, 0) ccw construction
  arc A224 (-43.0051, -16.6019) -> (-44.22, -19.3042) centre (-42.3871, -18.504) ccw construction
  line L56 (-32.5345, -32.6583) -> (-14.0602, -16.0239) construction
  arc A225 (-10.8948, -18.3237) -> (-14.0602, -16.0239) centre (-12.7219, -17.5102) ccw construction
  line L57 (-10.8948, -18.3237) -> (-21.0062, -41.0342) construction
  arc A226 (-23.8207, -41.96) -> (-21.0062, -41.0342) centre (-22.8333, -40.2207) ccw construction
  arc A227 (-32.5453, -35.6211) -> (-23.8207, -41.96) centre (0, 0) ccw construction
  arc A228 (-32.5345, -32.6583) -> (-32.5453, -35.6211) centre (-31.1963, -34.1446) ccw construction
  line L58 (-52.841, 6.5871) -> (-56.5622, 7.051) construction
  arc A229 (-52.841, 6.5871) -> (-53.2045, 2.2001) centre (0, 0) ccw construction
  line L59 (-56.9513, 2.355) -> (-53.2045, 2.2001) construction
  line L60 (-60, 1.2454) -> (-56.9513, 2.355) construction
  line L61 (-60, -1.2454) -> (-60, 1.2454) construction
  line L62 (-56.9513, -2.355) -> (-60, -1.2454) construction
  line L63 (-53.2045, -2.2001) -> (-56.9513, -2.355) construction
  arc A230 (-53.2045, -2.2001) -> (-52.841, -6.5871) centre (0, 0) ccw construction
  line L64 (-56.5622, -7.051) -> (-52.841, -6.5871) construction
  line L65 (-59.3867, -8.6473) -> (-56.5622, -7.051) construction
  line L66 (-58.9767, -11.1041) -> (-59.3867, -8.6473) construction
  line L67 (-55.787, -11.6968) -> (-58.9767, -11.1041) construction
  line L68 (-52.1168, -10.9272) -> (-55.787, -11.6968) construction
  arc A231 (-52.1168, -10.9272) -> (-51.0361, -15.1946) centre (0, 0) ccw construction
  line L69 (-54.6302, -16.2647) -> (-51.0361, -15.1946) construction
  line L70 (-57.1534, -18.3041) -> (-54.6302, -16.2647) construction
  line L71 (-56.3447, -20.6599) -> (-57.1534, -18.3041) construction
  line L72 (-53.1009, -20.7195) -> (-56.3447, -20.6599) construction
  line L73 (-49.6074, -19.3563) -> (-53.1009, -20.7195) construction
  arc A232 (-49.6074, -19.3563) -> (-47.8391, -23.3877) centre (0, 0) ccw construction
  line L74 (-51.2081, -25.0347) -> (-47.8391, -23.3877) construction
  line L75 (-53.3612, -27.4616) -> (-51.2081, -25.0347) construction
  line L76 (-52.1757, -29.6521) -> (-53.3612, -27.4616) construction
  line L77 (-48.9663, -29.177) -> (-52.1757, -29.6521) construction
  line L78 (-45.7449, -27.2575) -> (-48.9663, -29.177) construction
  arc A233 (-45.7449, -27.2575) -> (-43.3372, -30.9427) centre (0, 0) ccw construction
  line L79 (-46.3891, -33.1218) -> (-43.3372, -30.9427) construction
  line L80 (-48.1134, -35.87) -> (-46.3891, -33.1218) construction
  line L81 (-46.5835, -37.8355) -> (-48.1134, -35.87) construction
  line L82 (-43.4961, -36.8387) -> (-46.5835, -37.8355) construction
  line L83 (-40.6345, -34.4151) -> (-43.4961, -36.8387) construction
  arc A234 (-40.6345, -34.4151) -> (-37.6531, -37.6538) centre (0, 0) ccw construction
  line L84 (-40.3047, -40.3055) -> (-37.6531, -37.6538) construction
  line L85 (-41.5531, -43.3) -> (-40.3047, -40.3055) construction
  line L86 (-39.7206, -44.9869) -> (-41.5531, -43.3) construction
  line L87 (-36.8395, -43.4955) -> (-39.7206, -44.9869) construction
  line L88 (-34.4158, -40.6339) -> (-36.8395, -43.4955) construction
  arc A235 (-34.4158, -40.6339) -> (-30.9419, -43.3377) centre (0, 0) ccw construction
  line L89 (-33.121, -46.3897) -> (-30.9419, -43.3377) construction
  line L90 (-33.8595, -49.5488) -> (-33.121, -46.3897) construction
  line L91 (-31.7743, -50.9111) -> (-33.8595, -49.5488) construction
  line L92 (-29.1779, -48.9658) -> (-31.7743, -50.9111) construction
  line L93 (-27.2583, -45.7444) -> (-29.1779, -48.9658) construction
  arc A236 (-27.2583, -45.7444) -> (-23.3868, -47.8395) centre (0, 0) ccw construction
  line L94 (-25.0337, -51.2085) -> (-23.3868, -47.8395) construction
  line L95 (-25.2422, -54.4461) -> (-25.0337, -51.2085) construction
  line L96 (-22.9612, -55.4467) -> (-25.2422, -54.4461) construction
  line L97 (-20.7204, -53.1005) -> (-22.9612, -55.4467) construction
  line L98 (-19.3573, -49.607) -> (-20.7204, -53.1005) construction
  arc A237 (-19.3573, -49.607) -> (-15.1937, -51.0364) centre (0, 0) ccw construction
  line L99 (-16.2637, -54.6305) -> (-15.1937, -51.0364) construction
  line L100 (-15.9364, -57.8583) -> (-16.2637, -54.6305) construction
  line L101 (-13.5219, -58.4697) -> (-15.9364, -57.8583) construction
  line L102 (-11.6978, -55.7868) -> (-13.5219, -58.4697) construction
  line L103 (-10.9282, -52.1166) -> (-11.6978, -55.7868) construction
  arc A238 (-10.9282, -52.1166) -> (-6.5861, -52.8411) centre (0, 0) ccw construction
  line L104 (-7.05, -56.5623) -> (-6.5861, -52.8411) construction
  line L105 (-6.1959, -59.6922) -> (-7.05, -56.5623) construction
  line L106 (-3.7136, -59.8979) -> (-6.1959, -59.6922) construction
  line L107 (-2.356, -56.9513) -> (-3.7136, -59.8979) construction
  line L108 (-2.201, -53.2045) -> (-2.356, -56.9513) construction
  arc A239 (-2.201, -53.2045) -> (2.201, -53.2045) centre (0, 0) ccw construction
  line L109 (2.356, -56.9513) -> (2.201, -53.2045) construction
  line L110 (3.7136, -59.8979) -> (2.356, -56.9513) construction
  line L111 (6.1959, -59.6922) -> (3.7136, -59.8979) construction
  line L112 (7.05, -56.5623) -> (6.1959, -59.6922) construction
  line L113 (6.5861, -52.8411) -> (7.05, -56.5623) construction
  arc A240 (6.5861, -52.8411) -> (10.9282, -52.1166) centre (0, 0) ccw construction
  line L114 (11.6978, -55.7868) -> (10.9282, -52.1166) construction
  line L115 (13.5219, -58.4697) -> (11.6978, -55.7868) construction
  line L116 (15.9364, -57.8583) -> (13.5219, -58.4697) construction
  line L117 (16.2637, -54.6305) -> (15.9364, -57.8583) construction
  line L118 (15.1937, -51.0364) -> (16.2637, -54.6305) construction
  arc A241 (15.1937, -51.0364) -> (19.3573, -49.607) centre (0, 0) ccw construction
  line L119 (20.7204, -53.1005) -> (19.3573, -49.607) construction
  line L120 (22.9612, -55.4467) -> (20.7204, -53.1005) construction
  line L121 (25.2422, -54.4461) -> (22.9612, -55.4467) construction
  line L122 (25.0337, -51.2085) -> (25.2422, -54.4461) construction
  line L123 (23.3868, -47.8395) -> (25.0337, -51.2085) construction
  arc A242 (23.3868, -47.8395) -> (27.2583, -45.7444) centre (0, 0) ccw construction
  line L124 (29.1779, -48.9658) -> (27.2583, -45.7444) construction
  line L125 (31.7743, -50.9111) -> (29.1779, -48.9658) construction
  line L126 (33.8595, -49.5488) -> (31.7743, -50.9111) construction
  line L127 (33.121, -46.3897) -> (33.8595, -49.5488) construction
  line L128 (30.9419, -43.3377) -> (33.121, -46.3897) construction
  arc A243 (30.9419, -43.3377) -> (34.4158, -40.6339) centre (0, 0) ccw construction
  line L129 (36.8395, -43.4955) -> (34.4158, -40.6339) construction
  line L130 (39.7206, -44.9869) -> (36.8395, -43.4955) construction
  line L131 (41.5531, -43.3) -> (39.7206, -44.9869) construction
  line L132 (40.3047, -40.3055) -> (41.5531, -43.3) construction
  line L133 (37.6531, -37.6538) -> (40.3047, -40.3055) construction
  arc A244 (37.6531, -37.6538) -> (40.6345, -34.4151) centre (0, 0) ccw construction
  line L134 (43.4961, -36.8387) -> (40.6345, -34.4151) construction
  line L135 (46.5835, -37.8355) -> (43.4961, -36.8387) construction
  line L136 (48.1134, -35.87) -> (46.5835, -37.8355) construction
  line L137 (46.3891, -33.1218) -> (48.1134, -35.87) construction
  line L138 (43.3372, -30.9427) -> (46.3891, -33.1218) construction
  arc A245 (43.3372, -30.9427) -> (45.7449, -27.2575) centre (0, 0) ccw construction
  line L139 (48.9663, -29.177) -> (45.7449, -27.2575) construction
  line L140 (52.1757, -29.6521) -> (48.9663, -29.177) construction
  line L141 (53.3612, -27.4616) -> (52.1757, -29.6521) construction
  line L142 (51.2081, -25.0347) -> (53.3612, -27.4616) construction
  line L143 (47.8391, -23.3877) -> (51.2081, -25.0347) construction
  arc A246 (47.8391, -23.3877) -> (49.6074, -19.3563) centre (0, 0) ccw construction
  line L144 (53.1009, -20.7195) -> (49.6074, -19.3563) construction
  line L145 (56.3447, -20.6599) -> (53.1009, -20.7195) construction
  line L146 (57.1534, -18.3041) -> (56.3447, -20.6599) construction
  line L147 (54.6302, -16.2647) -> (57.1534, -18.3041) construction
  line L148 (51.0361, -15.1946) -> (54.6302, -16.2647) construction
  arc A247 (51.0361, -15.1946) -> (52.1168, -10.9272) centre (0, 0) ccw construction
  line L149 (55.787, -11.6968) -> (52.1168, -10.9272) construction
  line L150 (58.9767, -11.1041) -> (55.787, -11.6968) construction
  line L151 (59.3867, -8.6473) -> (58.9767, -11.1041) construction
  line L152 (56.5622, -7.051) -> (59.3867, -8.6473) construction
  line L153 (52.841, -6.5871) -> (56.5622, -7.051) construction
  arc A248 (52.841, -6.5871) -> (53.2045, -2.2001) centre (0, 0) ccw construction
  line L154 (56.9513, -2.355) -> (53.2045, -2.2001) construction
  line L155 (60, -1.2454) -> (56.9513, -2.355) construction
  line L156 (60, 1.2454) -> (60, -1.2454) construction
  line L157 (56.9513, 2.355) -> (60, 1.2454) construction
  line L158 (53.2045, 2.2001) -> (56.9513, 2.355) construction
  arc A249 (53.2045, 2.2001) -> (52.841, 6.5871) centre (0, 0) ccw construction
  line L159 (56.5622, 7.051) -> (52.841, 6.5871) construction
  line L160 (59.3867, 8.6473) -> (56.5622, 7.051) construction
  line L161 (58.9767, 11.1041) -> (59.3867, 8.6473) construction
  line L162 (55.787, 11.6968) -> (58.9767, 11.1041) construction
  line L163 (52.1168, 10.9272) -> (55.787, 11.6968) construction
  arc A250 (52.1168, 10.9272) -> (51.0361, 15.1946) centre (0, 0) ccw construction
  line L164 (54.6302, 16.2647) -> (51.0361, 15.1946) construction
  line L165 (57.1534, 18.3041) -> (54.6302, 16.2647) construction
  line L166 (56.3447, 20.6599) -> (57.1534, 18.3041) construction
  line L167 (53.1009, 20.7195) -> (56.3447, 20.6599) construction
  line L168 (49.6074, 19.3563) -> (53.1009, 20.7195) construction
  arc A251 (49.6074, 19.3563) -> (47.8391, 23.3877) centre (0, 0) ccw construction
  line L169 (51.2081, 25.0347) -> (47.8391, 23.3877) construction
  line L170 (53.3612, 27.4616) -> (51.2081, 25.0347) construction
  line L171 (52.1757, 29.6521) -> (53.3612, 27.4616) construction
  line L172 (48.9663, 29.177) -> (52.1757, 29.6521) construction
  line L173 (45.7449, 27.2575) -> (48.9663, 29.177) construction
  arc A252 (45.7449, 27.2575) -> (43.3372, 30.9427) centre (0, 0) ccw construction
  line L174 (46.3891, 33.1218) -> (43.3372, 30.9427) construction
  line L175 (48.1134, 35.87) -> (46.3891, 33.1218) construction
  line L176 (46.5835, 37.8355) -> (48.1134, 35.87) construction
  line L177 (43.4961, 36.8387) -> (46.5835, 37.8355) construction
  line L178 (40.6345, 34.4151) -> (43.4961, 36.8387) construction
  arc A253 (40.6345, 34.4151) -> (37.6531, 37.6538) centre (0, 0) ccw construction